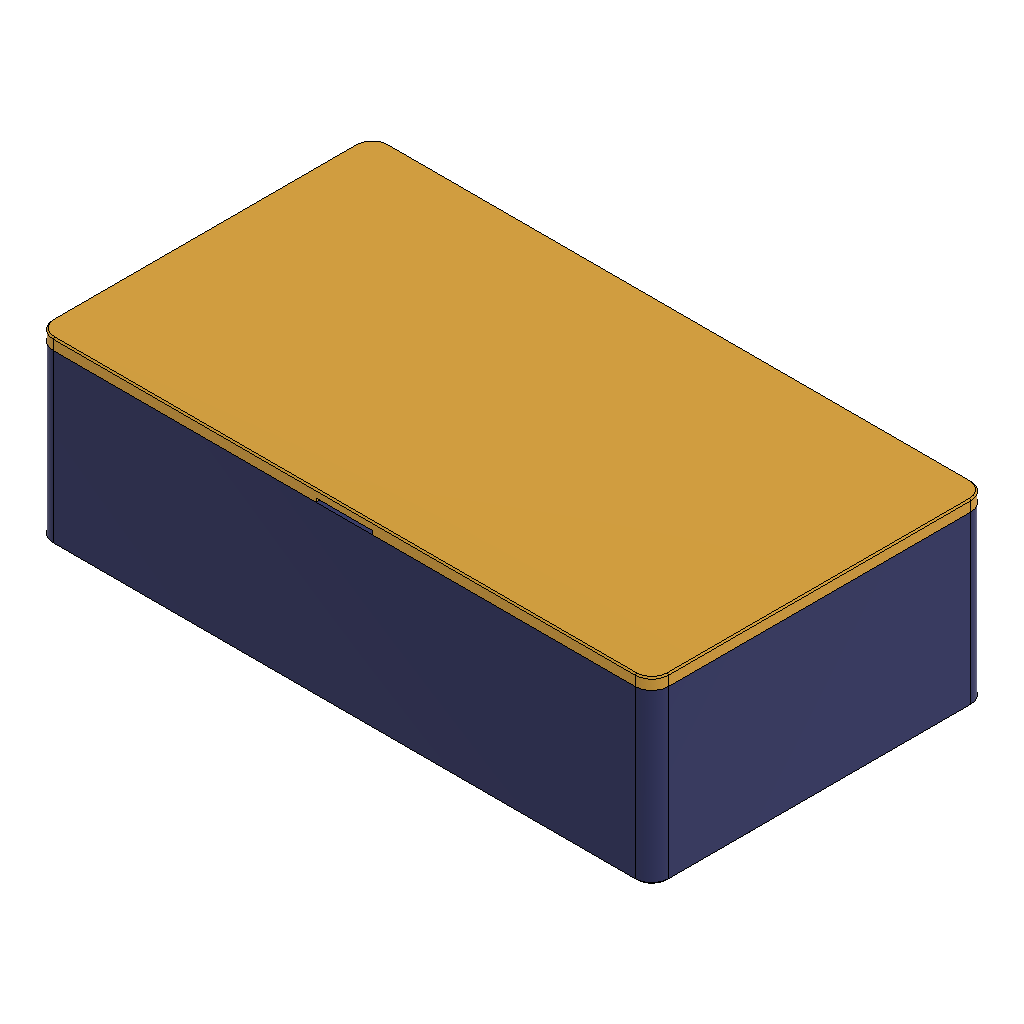
codex snap-fit (Autodesk Fusion 360 design; units mm, degrees)
part number: 2026-10-20-23-35-35-294
Autodesk Fusion 360 part; units mm, degrees
sketch "Box footprint - length x width" plane through (0, 0, 0) normal (0, 0, 1) x (1, 0, 0)
  line L0 (0, 0) -> (110, 0)
  line L1 (110, 0) -> (110, 60)
  line L2 (110, 60) -> (0, 60)
  line L3 (0, 60) -> (0, 0)
  dimension "d5" = 110
  dimension "d6" = 60
  constraint horizontal L0
  constraint horizontal L2
  constraint vertical L1
  constraint vertical L3
  measures "d5" horizontal distance of L0.start L0.end
  measures "d6" vertical distance of L0.end L1.end
extrude "Box outside - height" add sketch "Box footprint - length x width" along normal blind 30 makes body 1
shell "Open top - wall_thickness" thickness 2 removed faces 1 at (36.6667, 40, 30) on bodies 1
fillet "Inside edges - inside_fillet" radius 1 8 edges at (55, 58, 2) (108, 58, 16) (2, 58, 16) (108, 30, 2) (108, 2, 16) (55, 2, 2) (2, 2, 16) (2, 30, 2) on bodies 1
fillet "Outside vertical edges - outside_fillet" radius 3 4 edges at (0, 60, 15) (110, 60, 15) (110, 0, 15) (0, 0, 15) on bodies 1
ref_plane "WorkPlane1" through (0, 0, 30) normal (0, 0, 1) x (1, 0, 0)
sketch "Lid footprint - length x width" plane through (0, 0, 30) normal (0, 0, 1) x (1, 0, 0)
  line L0 (0, 0) -> (110, 0)
  line L1 (110, 0) -> (110, 60)
  line L2 (110, 60) -> (0, 60)
  line L3 (0, 60) -> (0, 0)
  dimension "d25" = 110
  dimension "d26" = 60
  constraint horizontal L0
  constraint horizontal L2
  constraint vertical L1
  constraint vertical L3
  measures "d25" horizontal distance of L0.start L0.end
  measures "d26" vertical distance of L0.end L1.end
extrude "Lid plate - wall_thickness" add sketch "Lid footprint - length x width" along normal blind 2 separate body makes body 2
fillet "Lid corners - outside_fillet" radius 3 4 edges at (0, 60, 31) (110, 60, 31) (110, 0, 31) (0, 0, 31) on bodies 2
ref_plane "WorkPlane61" through (0, 0, 30) normal (0, 0, 1) x (1, 0, 0)
sketch "Continuous shallow locating rim" plane through (0, 0, 30) normal (0, 0, 1) x (1, 0, 0)
  line L0 (2.2, 2.2) -> (107.8, 2.2)
  line L1 (107.8, 2.2) -> (107.8, 57.8)
  line L2 (107.8, 57.8) -> (2.2, 57.8)
  line L3 (2.2, 57.8) -> (2.2, 2.2)
  line L4 (4.2, 4.2) -> (105.8, 4.2)
  line L5 (105.8, 4.2) -> (105.8, 55.8)
  line L6 (105.8, 55.8) -> (4.2, 55.8)
  line L7 (4.2, 55.8) -> (4.2, 4.2)
  dimension "d541" = 2.2
  dimension "d542" = 2.2
  dimension "d543" = 105.6
  dimension "d544" = 55.6
  dimension "d545" = 4.2
  dimension "d546" = 4.2
  dimension "d547" = 101.6
  dimension "d548" = 51.6
  constraint horizontal L0
  constraint horizontal L2
  constraint vertical L1
  constraint vertical L3
  constraint horizontal L4
  constraint horizontal L6
  constraint vertical L5
  constraint vertical L7
  measures "d541" horizontal distance of origin L0.start
  measures "d542" vertical distance of origin L0.start
  measures "d543" horizontal distance of L0.start L0.end
  measures "d544" vertical distance of L0.end L1.end
  measures "d545" horizontal distance of origin L4.start
  measures "d546" vertical distance of origin L4.start
  measures "d547" horizontal distance of L4.start L4.end
  measures "d548" vertical distance of L4.end L5.end
extrude "Continuous locating rim - shallow" add sketch "Continuous shallow locating rim" against normal blind 2 separate body makes body 3
fillet "Locating rim cavity-matching corners" radius 0.8 4 edges at (2.2, 2.2, 29) (107.8, 2.2, 29) (107.8, 57.8, 29) (2.2, 57.8, 29) on bodies 3
combine "Join continuous locating rim to lid" operation add target body 2 tool bodies 3
fillet "Continuous inside rim-to-lid fillet" radius 1 4 edges at (55, 55.8, 30) (105.8, 30, 30) (55, 4.2, 30) (4.2, 30, 30) on bodies 2
ref_plane "WorkPlane62" through (0, 0, 28) normal (0, 0, 1) x (1, 0, 0)
sketch "Front snap 1 tapered root" plane through (0, 0, 28) normal (0, 0, 1) x (1, 0, 0)
  line L0 (20.625, 2.2) -> (34.375, 2.2)
  line L1 (34.375, 2.2) -> (34.375, 4.2)
  line L2 (34.375, 4.2) -> (20.625, 4.2)
  line L3 (20.625, 4.2) -> (20.625, 2.2)
  dimension "d557" = 20.625
  dimension "d558" = 2.2
  dimension "d559" = 13.75
  dimension "d560" = 2
  constraint horizontal L0
  constraint horizontal L2
  constraint vertical L1
  constraint vertical L3
  measures "d557" horizontal distance of origin L0.start
  measures "d558" vertical distance of origin L0.start
  measures "d559" horizontal distance of L0.start L0.end
  measures "d560" vertical distance of L0.end L1.end
ref_plane "WorkPlane63" through (0, 0, 22) normal (0, 0, 1) x (1, 0, 0)
sketch "Front snap 1 tapered tip" plane through (0, 0, 22) normal (0, 0, 1) x (1, 0, 0)
  line L0 (20.625, 2.2) -> (34.375, 2.2)
  line L1 (34.375, 2.2) -> (34.375, 3.45)
  line L2 (34.375, 3.45) -> (20.625, 3.45)
  line L3 (20.625, 3.45) -> (20.625, 2.2)
  dimension "d563" = 20.625
  dimension "d564" = 2.2
  dimension "d565" = 13.75
  dimension "d566" = 1.25
  constraint horizontal L0
  constraint horizontal L2
  constraint vertical L1
  constraint vertical L3
  measures "d563" horizontal distance of origin L0.start
  measures "d564" vertical distance of origin L0.start
  measures "d565" horizontal distance of L0.start L0.end
  measures "d566" vertical distance of L0.end L1.end
loft "Front snap 1 tapered flexible tab" add profiles "Front snap 1 tapered root", "Front snap 1 tapered tip" section 1 section 2 bodies 2
ref_plane "WorkPlane64" through (0, 0, 28) normal (0, 0, 1) x (1, 0, 0)
sketch "Front snap 2 tapered root" plane through (0, 0, 28) normal (0, 0, 1) x (1, 0, 0)
  line L0 (75.625, 2.2) -> (89.375, 2.2)
  line L1 (89.375, 2.2) -> (89.375, 4.2)
  line L2 (89.375, 4.2) -> (75.625, 4.2)
  line L3 (75.625, 4.2) -> (75.625, 2.2)
  dimension "d569" = 75.625
  dimension "d570" = 2.2
  dimension "d571" = 13.75
  dimension "d572" = 2
  constraint horizontal L0
  constraint horizontal L2
  constraint vertical L1
  constraint vertical L3
  measures "d569" horizontal distance of origin L0.start
  measures "d570" vertical distance of origin L0.start
  measures "d571" horizontal distance of L0.start L0.end
  measures "d572" vertical distance of L0.end L1.end
ref_plane "WorkPlane65" through (0, 0, 22) normal (0, 0, 1) x (1, 0, 0)
sketch "Front snap 2 tapered tip" plane through (0, 0, 22) normal (0, 0, 1) x (1, 0, 0)
  line L0 (75.625, 2.2) -> (89.375, 2.2)
  line L1 (89.375, 2.2) -> (89.375, 3.45)
  line L2 (89.375, 3.45) -> (75.625, 3.45)
  line L3 (75.625, 3.45) -> (75.625, 2.2)
  dimension "d575" = 75.625
  dimension "d576" = 2.2
  dimension "d577" = 13.75
  dimension "d578" = 1.25
  constraint horizontal L0
  constraint horizontal L2
  constraint vertical L1
  constraint vertical L3
  measures "d575" horizontal distance of origin L0.start
  measures "d576" vertical distance of origin L0.start
  measures "d577" horizontal distance of L0.start L0.end
  measures "d578" vertical distance of L0.end L1.end
loft "Front snap 2 tapered flexible tab" add profiles "Front snap 2 tapered root", "Front snap 2 tapered tip" section 1 section 2 bodies 2
ref_plane "WorkPlane66" through (0, 0, 28) normal (0, 0, 1) x (1, 0, 0)
sketch "Back snap 1 tapered root" plane through (0, 0, 28) normal (0, 0, 1) x (1, 0, 0)
  line L0 (20.625, 55.8) -> (34.375, 55.8)
  line L1 (34.375, 55.8) -> (34.375, 57.8)
  line L2 (34.375, 57.8) -> (20.625, 57.8)
  line L3 (20.625, 57.8) -> (20.625, 55.8)
  dimension "d581" = 20.625
  dimension "d582" = 55.8
  dimension "d583" = 13.75
  dimension "d584" = 2
  constraint horizontal L0
  constraint horizontal L2
  constraint vertical L1
  constraint vertical L3
  measures "d581" horizontal distance of origin L0.start
  measures "d582" vertical distance of origin L0.start
  measures "d583" horizontal distance of L0.start L0.end
  measures "d584" vertical distance of L0.end L1.end
ref_plane "WorkPlane67" through (0, 0, 22) normal (0, 0, 1) x (1, 0, 0)
sketch "Back snap 1 tapered tip" plane through (0, 0, 22) normal (0, 0, 1) x (1, 0, 0)
  line L0 (20.625, 56.55) -> (34.375, 56.55)
  line L1 (34.375, 56.55) -> (34.375, 57.8)
  line L2 (34.375, 57.8) -> (20.625, 57.8)
  line L3 (20.625, 57.8) -> (20.625, 56.55)
  dimension "d587" = 20.625
  dimension "d588" = 56.55
  dimension "d589" = 13.75
  dimension "d590" = 1.25
  constraint horizontal L0
  constraint horizontal L2
  constraint vertical L1
  constraint vertical L3
  measures "d587" horizontal distance of origin L0.start
  measures "d588" vertical distance of origin L0.start
  measures "d589" horizontal distance of L0.start L0.end
  measures "d590" vertical distance of L0.end L1.end
loft "Back snap 1 tapered flexible tab" add profiles "Back snap 1 tapered root", "Back snap 1 tapered tip" section 1 section 2 bodies 2
ref_plane "WorkPlane68" through (0, 0, 28) normal (0, 0, 1) x (1, 0, 0)
sketch "Back snap 2 tapered root" plane through (0, 0, 28) normal (0, 0, 1) x (1, 0, 0)
  line L0 (75.625, 55.8) -> (89.375, 55.8)
  line L1 (89.375, 55.8) -> (89.375, 57.8)
  line L2 (89.375, 57.8) -> (75.625, 57.8)
  line L3 (75.625, 57.8) -> (75.625, 55.8)
  dimension "d593" = 75.625
  dimension "d594" = 55.8
  dimension "d595" = 13.75
  dimension "d596" = 2
  constraint horizontal L0
  constraint horizontal L2
  constraint vertical L1
  constraint vertical L3
  measures "d593" horizontal distance of origin L0.start
  measures "d594" vertical distance of origin L0.start
  measures "d595" horizontal distance of L0.start L0.end
  measures "d596" vertical distance of L0.end L1.end
ref_plane "WorkPlane69" through (0, 0, 22) normal (0, 0, 1) x (1, 0, 0)
sketch "Back snap 2 tapered tip" plane through (0, 0, 22) normal (0, 0, 1) x (1, 0, 0)
  line L0 (75.625, 56.55) -> (89.375, 56.55)
  line L1 (89.375, 56.55) -> (89.375, 57.8)
  line L2 (89.375, 57.8) -> (75.625, 57.8)
  line L3 (75.625, 57.8) -> (75.625, 56.55)
  dimension "d599" = 75.625
  dimension "d600" = 56.55
  dimension "d601" = 13.75
  dimension "d602" = 1.25
  constraint horizontal L0
  constraint horizontal L2
  constraint vertical L1
  constraint vertical L3
  measures "d599" horizontal distance of origin L0.start
  measures "d600" vertical distance of origin L0.start
  measures "d601" horizontal distance of L0.start L0.end
  measures "d602" vertical distance of L0.end L1.end
loft "Back snap 2 tapered flexible tab" add profiles "Back snap 2 tapered root", "Back snap 2 tapered tip" section 1 section 2 bodies 2
fillet "Eight strengthened rim-to-tab end transitions" radius 1 8 edges at (75.625, 56.8, 28) (89.375, 56.8, 28) (89.375, 3.2, 28) (20.625, 56.8, 28) (34.375, 56.8, 28) (75.625, 3.2, 28) (34.375, 3.2, 28) (20.625, 3.2, 28) on bodies 2
ref_plane "WorkPlane70" through (20.425, 0, 0) normal (1, 0, 0) x (0, 1, 0)
sketch "Front snap 1 mating groove" plane through (20.425, 0, 0) normal (1, 0, 0) x (0, 0, -1)
  circle A0 centre (-23.5, 2.2) radius 0.8
  dimension "d607" = 23.5
  dimension "d608" = 2.2
  dimension "d609" = 0.8
  measures "d607" horizontal distance of origin A0.centre
  measures "d608" vertical distance of origin A0.centre
  measures "d609" radius of A0
extrude "Front snap 1 groove" cut sketch "Front snap 1 mating groove" along normal blind 14.15 bodies 1
ref_plane "WorkPlane71" through (75.425, 0, 0) normal (1, 0, 0) x (0, 1, 0)
sketch "Front snap 2 mating groove" plane through (75.425, 0, 0) normal (1, 0, 0) x (0, 0, -1)
  circle A0 centre (-23.5, 2.2) radius 0.8
  dimension "d614" = 23.5
  dimension "d615" = 2.2
  dimension "d616" = 0.8
  measures "d614" horizontal distance of origin A0.centre
  measures "d615" vertical distance of origin A0.centre
  measures "d616" radius of A0
extrude "Front snap 2 groove" cut sketch "Front snap 2 mating groove" along normal blind 14.15 bodies 1
ref_plane "WorkPlane72" through (20.425, 0, 0) normal (1, 0, 0) x (0, 1, 0)
sketch "Back snap 1 mating groove" plane through (20.425, 0, 0) normal (1, 0, 0) x (0, 0, -1)
  circle A0 centre (-23.5, 57.8) radius 0.8
  dimension "d621" = 23.5
  dimension "d622" = 57.8
  dimension "d623" = 0.8
  measures "d621" horizontal distance of origin A0.centre
  measures "d622" vertical distance of origin A0.centre
  measures "d623" radius of A0
extrude "Back snap 1 groove" cut sketch "Back snap 1 mating groove" along normal blind 14.15 bodies 1
ref_plane "WorkPlane73" through (75.425, 0, 0) normal (1, 0, 0) x (0, 1, 0)
sketch "Back snap 2 mating groove" plane through (75.425, 0, 0) normal (1, 0, 0) x (0, 0, -1)
  circle A0 centre (-23.5, 57.8) radius 0.8
  dimension "d628" = 23.5
  dimension "d629" = 57.8
  dimension "d630" = 0.8
  measures "d628" horizontal distance of origin A0.centre
  measures "d629" vertical distance of origin A0.centre
  measures "d630" radius of A0
extrude "Back snap 2 groove" cut sketch "Back snap 2 mating groove" along normal blind 14.15 bodies 1
ref_plane "WorkPlane74" through (20.625, 0, 0) normal (1, 0, 0) x (0, 1, 0)
sketch "Front snap 1 semicircular bead" plane through (20.625, 0, 0) normal (1, 0, 0) x (0, 0, -1)
  circle A0 centre (-23.5, 2.2) radius 0.75
  dimension "d635" = 23.5
  dimension "d636" = 2.2
  dimension "d637" = 0.75
  measures "d635" horizontal distance of origin A0.centre
  measures "d636" vertical distance of origin A0.centre
  measures "d637" radius of A0
extrude "Front snap 1 retaining bead" add sketch "Front snap 1 semicircular bead" along normal blind 13.75 bodies 2
ref_plane "WorkPlane75" through (75.625, 0, 0) normal (1, 0, 0) x (0, 1, 0)
sketch "Front snap 2 semicircular bead" plane through (75.625, 0, 0) normal (1, 0, 0) x (0, 0, -1)
  circle A0 centre (-23.5, 2.2) radius 0.75
  dimension "d642" = 23.5
  dimension "d643" = 2.2
  dimension "d644" = 0.75
  measures "d642" horizontal distance of origin A0.centre
  measures "d643" vertical distance of origin A0.centre
  measures "d644" radius of A0
extrude "Front snap 2 retaining bead" add sketch "Front snap 2 semicircular bead" along normal blind 13.75 bodies 2
ref_plane "WorkPlane76" through (20.625, 0, 0) normal (1, 0, 0) x (0, 1, 0)
sketch "Back snap 1 semicircular bead" plane through (20.625, 0, 0) normal (1, 0, 0) x (0, 0, -1)
  circle A0 centre (-23.5, 57.8) radius 0.75
  dimension "d649" = 23.5
  dimension "d650" = 57.8
  dimension "d651" = 0.75
  measures "d649" horizontal distance of origin A0.centre
  measures "d650" vertical distance of origin A0.centre
  measures "d651" radius of A0
extrude "Back snap 1 retaining bead" add sketch "Back snap 1 semicircular bead" along normal blind 13.75 bodies 2
ref_plane "WorkPlane77" through (75.625, 0, 0) normal (1, 0, 0) x (0, 1, 0)
sketch "Back snap 2 semicircular bead" plane through (75.625, 0, 0) normal (1, 0, 0) x (0, 0, -1)
  circle A0 centre (-23.5, 57.8) radius 0.75
  dimension "d656" = 23.5
  dimension "d657" = 57.8
  dimension "d658" = 0.75
  measures "d656" horizontal distance of origin A0.centre
  measures "d657" vertical distance of origin A0.centre
  measures "d658" radius of A0
extrude "Back snap 2 retaining bead" add sketch "Back snap 2 semicircular bead" along normal blind 13.75 bodies 2
ref_plane "WorkPlane96" through (50, 0, 0) normal (1, 0, 0) x (0, 1, 0)
sketch "Front beveled pick-entry profile" plane through (50, 0, 0) normal (1, 0, 0) x (0, 0, -1)
  line L0 (-30, 0) -> (-30.6667, 0)
  line L1 (-30.6667, 0) -> (-30, 2)
  line L2 (-30, 2) -> (-30, 0)
  dimension "d810" = 30
  dimension "d811" = 0.6667
  dimension "d812" = 2
  constraint horizontal L0
  constraint vertical L2
  constraint horizontal origin L0.start
  measures "d810" horizontal distance of origin L0.start
  measures "d811" horizontal distance of L0.start L0.end
  measures "d812" vertical distance of L0.start L1.end
extrude "Front beveled pick-entry notch between snaps" cut sketch "Front beveled pick-entry profile" along normal blind 10 bodies 2
ref_plane "WorkPlane97" through (50, 0, 0) normal (1, 0, 0) x (0, 1, 0)
sketch "Back beveled pick-entry profile" plane through (50, 0, 0) normal (1, 0, 0) x (0, 0, -1)
  line L0 (-30, 60) -> (-30.6667, 60)
  line L1 (-30.6667, 60) -> (-30, 58)
  line L2 (-30, 58) -> (-30, 60)
  dimension "d817" = 30
  dimension "d818" = 60
  dimension "d819" = 0.6667
  dimension "d820" = 2
  constraint horizontal L0
  constraint vertical L2
  measures "d817" horizontal distance of origin L0.start
  measures "d818" vertical distance of origin L0.start
  measures "d819" horizontal distance of L0.start L0.end
  measures "d820" vertical distance of L0.start L1.end
extrude "Back beveled pick-entry notch between snaps" cut sketch "Back beveled pick-entry profile" along normal blind 10 bodies 2
chamfer "Chamfer1" distance 0.25 angle 45 8 edges at (55, 0, 32) (109.1213, 0.8787, 32) (110, 30, 32) (109.1213, 59.1213, 32) (55, 60, 32) (0.8787, 59.1213, 32) (0, 30, 32) (0.8787, 0.8787, 32) tangent chain off on bodies 1 2
chamfer "Chamfer1" distance 0.25 angle 45 8 edges at (55, 0, 0) (109.1213, 0.8787, 0) (110, 30, 0) (109.1213, 59.1213, 0) (55, 60, 0) (0.8787, 59.1213, 0) (0, 30, 0) (0.8787, 0.8787, 0) tangent chain off on bodies 1 2
equation "length = 110 mm" comment "Outside length"
equation "width = 60 mm" comment "Outside width"
equation "height = 30 mm" comment "Outside height"
equation "wall_thickness = 2 mm" comment "Side walls and bottom thickness"
equation "d5 = length"
equation "d6 = width"
equation "d7 = height"
equation "d9 = wall_thickness"
equation "inside_fillet = wall_thickness / 2" comment "Radius for four inside vertical and four inside bottom edges"
equation "d12 = inside_fillet"
equation "outside_fillet = 3 mm" comment "Radius for the four vertical outside edges"
equation "d15 = outside_fillet"
equation "lid_gap = 0.2 mm" comment "Lateral locating-rim/tab-to-wall clearance per side; seam and groove clearances now separate"
equation "lid_thickness = wall_thickness" comment "Lid plate thickness follows box wall"
equation "lip_depth = 4 * wall_thickness" comment "Length of the four flexible insertion tabs"
equation "lip_radius = 3 * wall_thickness / 8" comment "Retaining bead radius; increased for stronger engagement; groove uses snap_clearance"
equation "snap_thickness = 5 * wall_thickness / 8" comment "Tapered tab thickness at free tip; root uses snap_root_thickness"
equation "snap_length = length / 8" comment "Width of each of the four tabs; two per long side"
equation "d23 = height + lid_seam_gap"
equation "d25 = abs(( length ) - ( 0 mm ))"
equation "d26 = abs(( width ) - ( 0 mm ))"
equation "d27 = lid_thickness"
equation "d30 = outside_fillet"
equation "snap_root_fillet = wall_thickness / 2" comment "Rounded end transitions where each tab emerges from the locating rim"
equation "snap_offset = length / 4" comment "Tab center distance from each short end"
equation "rim_depth = wall_thickness" comment "Shallow continuous locating-rim insertion depth"
equation "rim_thickness = wall_thickness" comment "Continuous locating-rim width and nominal tab-root thickness"
equation "rim_corner_radius = inside_fillet - lid_gap" comment "Outer locating-rim corner radius matching the offset box cavity"
equation "snap_root_thickness = rim_thickness" comment "Tab thickness at rim attachment"
equation "rim_inside_fillet = wall_thickness / 2" comment "Continuous inside rim-to-lid-plate fillet"
equation "d539 = height + lid_seam_gap"
equation "d541 = abs(wall_thickness + lid_gap)"
equation "d542 = abs(wall_thickness + lid_gap)"
equation "d543 = abs(( length - wall_thickness - lid_gap ) - ( wall_thickness + lid_gap ))"
equation "d544 = abs(( width - wall_thickness - lid_gap ) - ( wall_thickness + lid_gap ))"
equation "d545 = abs(wall_thickness + lid_gap + rim_thickness)"
equation "d546 = abs(wall_thickness + lid_gap + rim_thickness)"
equation "d547 = abs(( length - wall_thickness - lid_gap - rim_thickness ) - ( wall_thickness + lid_gap + rim_thickness ))"
equation "d548 = abs(( width - wall_thickness - lid_gap - rim_thickness ) - ( wall_thickness + lid_gap + rim_thickness ))"
equation "d549 = -rim_depth"
equation "d552 = rim_corner_radius"
equation "d554 = rim_inside_fillet"
equation "d555 = height + lid_seam_gap - rim_depth"
equation "d557 = abs(( snap_offset ) - snap_length / 2)"
equation "d558 = abs(wall_thickness + lid_gap)"
equation "d559 = abs(( ( snap_offset ) + snap_length / 2 ) - ( ( snap_offset ) - snap_length / 2 ))"
equation "d560 = abs(( wall_thickness + lid_gap + snap_root_thickness ) - ( wall_thickness + lid_gap ))"
equation "d561 = height + lid_seam_gap - lip_depth"
equation "d563 = abs(( snap_offset ) - snap_length / 2)"
equation "d564 = abs(wall_thickness + lid_gap)"
equation "d565 = abs(( ( snap_offset ) + snap_length / 2 ) - ( ( snap_offset ) - snap_length / 2 ))"
equation "d566 = abs(( wall_thickness + lid_gap + snap_thickness ) - ( wall_thickness + lid_gap ))"
equation "d567 = height + lid_seam_gap - rim_depth"
equation "d569 = abs(( length - snap_offset ) - snap_length / 2)"
equation "d570 = abs(wall_thickness + lid_gap)"
equation "d571 = abs(( ( length - snap_offset ) + snap_length / 2 ) - ( ( length - snap_offset ) - snap_length / 2 ))"
equation "d572 = abs(( wall_thickness + lid_gap + snap_root_thickness ) - ( wall_thickness + lid_gap ))"
equation "d573 = height + lid_seam_gap - lip_depth"
equation "d575 = abs(( length - snap_offset ) - snap_length / 2)"
equation "d576 = abs(wall_thickness + lid_gap)"
equation "d577 = abs(( ( length - snap_offset ) + snap_length / 2 ) - ( ( length - snap_offset ) - snap_length / 2 ))"
equation "d578 = abs(( wall_thickness + lid_gap + snap_thickness ) - ( wall_thickness + lid_gap ))"
equation "d579 = height + lid_seam_gap - rim_depth"
equation "d581 = abs(( snap_offset ) - snap_length / 2)"
equation "d582 = abs(width - wall_thickness - lid_gap - snap_root_thickness)"
equation "d583 = abs(( ( snap_offset ) + snap_length / 2 ) - ( ( snap_offset ) - snap_length / 2 ))"
equation "d584 = abs(( width - wall_thickness - lid_gap ) - ( width - wall_thickness - lid_gap - snap_root_thickness ))"
equation "d585 = height + lid_seam_gap - lip_depth"
equation "d587 = abs(( snap_offset ) - snap_length / 2)"
equation "d588 = abs(width - wall_thickness - lid_gap - snap_thickness)"
equation "d589 = abs(( ( snap_offset ) + snap_length / 2 ) - ( ( snap_offset ) - snap_length / 2 ))"
equation "d590 = abs(( width - wall_thickness - lid_gap ) - ( width - wall_thickness - lid_gap - snap_thickness ))"
equation "d591 = height + lid_seam_gap - rim_depth"
equation "d593 = abs(( length - snap_offset ) - snap_length / 2)"
equation "d594 = abs(width - wall_thickness - lid_gap - snap_root_thickness)"
equation "d595 = abs(( ( length - snap_offset ) + snap_length / 2 ) - ( ( length - snap_offset ) - snap_length / 2 ))"
equation "d596 = abs(( width - wall_thickness - lid_gap ) - ( width - wall_thickness - lid_gap - snap_root_thickness ))"
equation "d597 = height + lid_seam_gap - lip_depth"
equation "d599 = abs(( length - snap_offset ) - snap_length / 2)"
equation "d600 = abs(width - wall_thickness - lid_gap - snap_thickness)"
equation "d601 = abs(( ( length - snap_offset ) + snap_length / 2 ) - ( ( length - snap_offset ) - snap_length / 2 ))"
equation "d602 = abs(( width - wall_thickness - lid_gap ) - ( width - wall_thickness - lid_gap - snap_thickness ))"
equation "d604 = snap_root_fillet"
equation "d605 = ( snap_offset ) - snap_length / 2 - lid_gap"
equation "d607 = abs(-( height + lid_seam_gap - lip_depth + 2 * lip_radius ))"
equation "d608 = abs(( wall_thickness + lid_gap ))"
equation "d609 = lip_radius + snap_clearance"
equation "d610 = snap_length + 2 * lid_gap"
equation "d612 = ( length - snap_offset ) - snap_length / 2 - lid_gap"
equation "d614 = abs(-( height + lid_seam_gap - lip_depth + 2 * lip_radius ))"
equation "d615 = abs(( wall_thickness + lid_gap ))"
equation "d616 = lip_radius + snap_clearance"
equation "d617 = snap_length + 2 * lid_gap"
equation "d619 = ( snap_offset ) - snap_length / 2 - lid_gap"
equation "d621 = abs(-( height + lid_seam_gap - lip_depth + 2 * lip_radius ))"
equation "d622 = abs(( width - wall_thickness - lid_gap ))"
equation "d623 = lip_radius + snap_clearance"
equation "d624 = snap_length + 2 * lid_gap"
equation "d626 = ( length - snap_offset ) - snap_length / 2 - lid_gap"
equation "d628 = abs(-( height + lid_seam_gap - lip_depth + 2 * lip_radius ))"
equation "d629 = abs(( width - wall_thickness - lid_gap ))"
equation "d630 = lip_radius + snap_clearance"
equation "d631 = snap_length + 2 * lid_gap"
equation "d633 = ( snap_offset ) - snap_length / 2"
equation "d635 = abs(-( height + lid_seam_gap - lip_depth + 2 * lip_radius ))"
equation "d636 = abs(( wall_thickness + lid_gap ))"
equation "d637 = lip_radius"
equation "d638 = snap_length"
equation "d640 = ( length - snap_offset ) - snap_length / 2"
equation "d642 = abs(-( height + lid_seam_gap - lip_depth + 2 * lip_radius ))"
equation "d643 = abs(( wall_thickness + lid_gap ))"
equation "d644 = lip_radius"
equation "d645 = snap_length"
equation "d647 = ( snap_offset ) - snap_length / 2"
equation "d649 = abs(-( height + lid_seam_gap - lip_depth + 2 * lip_radius ))"
equation "d650 = abs(( width - wall_thickness - lid_gap ))"
equation "d651 = lip_radius"
equation "d652 = snap_length"
equation "d654 = ( length - snap_offset ) - snap_length / 2"
equation "d656 = abs(-( height + lid_seam_gap - lip_depth + 2 * lip_radius ))"
equation "d657 = abs(( width - wall_thickness - lid_gap ))"
equation "d658 = lip_radius"
equation "d659 = snap_length"
equation "lid_seam_gap = 0 mm" comment "Vertical gap under lid plate; zero seats the lid on the box rim"
equation "snap_clearance = 0.05 mm" comment "Radial bead-to-groove clearance, independent of locating clearance; controls vertical play"
equation "pry_width = 5 * wall_thickness" comment "Pick-entry notch width centered between the two long-side tabs"
equation "pry_depth = lid_thickness / 3" comment "Beveled recess height at lid outer edge"
equation "pry_reach = wall_thickness" comment "Bevel reach inward from lid edge; should stop before locating rim"
equation "d808 = length / 2 - pry_width / 2"
equation "d810 = height + lid_seam_gap"
equation "d811 = pry_depth"
equation "d812 = pry_reach"
equation "d813 = pry_width"
equation "d815 = length / 2 - pry_width / 2"
equation "d817 = height + lid_seam_gap"
equation "d818 = width"
equation "d819 = pry_depth"
equation "d820 = pry_reach"
equation "d821 = pry_width"
equation "bed_chamfer = 0.25 mm" comment "anti-elephant foot chamfer"
equation "d824 = bed_chamfer"
equation "d825 = bed_chamfer"
equation "d685 = abs(( ( length - snap_offset ) - ( release_width - release_height ) / 2 ))"
equation "d686 = abs(-( height + lid_gap - lip_depth + 2 * lip_radius ))"
equation "d687 = release_radius"
equation "d688 = wall_thickness + 2 * lid_gap"
equation "d692 = abs(( ( length - snap_offset ) + ( release_width - release_height ) / 2 ))"
equation "d693 = abs(-( height + lid_gap - lip_depth + 2 * lip_radius ))"
equation "d694 = release_radius"
equation "d695 = wall_thickness + 2 * lid_gap"
equation "d699 = abs(( ( length - snap_offset ) - ( release_width - release_height ) / 2 ))"
equation "d700 = abs(-( ( height + lid_gap - lip_depth + 2 * lip_radius ) - release_radius ))"
equation "d701 = abs(( ( ( length - snap_offset ) + ( release_width - release_height ) / 2 ) ) - ( ( ( length - snap_offset ) - ( release_width - release_height ) / 2 ) ))"
equation "d702 = abs(( -( ( height + lid_gap - lip_depth + 2 * lip_radius ) + release_radius ) ) - ( -( ( height + lid_gap - lip_depth + 2 * lip_radius ) - release_radius ) ))"
equation "d703 = wall_thickness + 2 * lid_gap"
equation "d705 = width - wall_thickness - lid_gap"
equation "d707 = abs(( ( snap_offset ) - ( release_width - release_height ) / 2 ))"
equation "d708 = abs(-( height + lid_gap - lip_depth + 2 * lip_radius ))"
equation "d709 = release_radius"
equation "d710 = wall_thickness + 2 * lid_gap"
equation "d712 = width - wall_thickness - lid_gap"
equation "d714 = abs(( ( snap_offset ) + ( release_width - release_height ) / 2 ))"
equation "d715 = abs(-( height + lid_gap - lip_depth + 2 * lip_radius ))"
equation "d716 = release_radius"
equation "d717 = wall_thickness + 2 * lid_gap"
equation "d719 = width - wall_thickness - lid_gap"
equation "d721 = abs(( ( snap_offset ) - ( release_width - release_height ) / 2 ))"
equation "d722 = abs(-( ( height + lid_gap - lip_depth + 2 * lip_radius ) - release_radius ))"
equation "d723 = abs(( ( ( snap_offset ) + ( release_width - release_height ) / 2 ) ) - ( ( ( snap_offset ) - ( release_width - release_height ) / 2 ) ))"
equation "d724 = abs(( -( ( height + lid_gap - lip_depth + 2 * lip_radius ) + release_radius ) ) - ( -( ( height + lid_gap - lip_depth + 2 * lip_radius ) - release_radius ) ))"
equation "d725 = wall_thickness + 2 * lid_gap"
equation "d727 = width - wall_thickness - lid_gap"
equation "d729 = abs(( ( length - snap_offset ) - ( release_width - release_height ) / 2 ))"
equation "d730 = abs(-( height + lid_gap - lip_depth + 2 * lip_radius ))"
equation "d731 = release_radius"
equation "d732 = wall_thickness + 2 * lid_gap"
equation "d734 = width - wall_thickness - lid_gap"
equation "d736 = abs(( ( length - snap_offset ) + ( release_width - release_height ) / 2 ))"
equation "d737 = abs(-( height + lid_gap - lip_depth + 2 * lip_radius ))"
equation "d738 = release_radius"
equation "d739 = wall_thickness + 2 * lid_gap"
equation "d741 = width - wall_thickness - lid_gap"
equation "d743 = abs(( ( length - snap_offset ) - ( release_width - release_height ) / 2 ))"
equation "d744 = abs(-( ( height + lid_gap - lip_depth + 2 * lip_radius ) - release_radius ))"
equation "d745 = abs(( ( ( length - snap_offset ) + ( release_width - release_height ) / 2 ) ) - ( ( ( length - snap_offset ) - ( release_width - release_height ) / 2 ) ))"
equation "d746 = abs(( -( ( height + lid_gap - lip_depth + 2 * lip_radius ) + release_radius ) ) - ( -( ( height + lid_gap - lip_depth + 2 * lip_radius ) - release_radius ) ))"
equation "d747 = wall_thickness + 2 * lid_gap"
equation "d749 = height - coupon_height"
equation "d751 = abs(snap_offset - snap_length / 2 - ( coupon_margin + coupon_end_clearance ))"
equation "d752 = abs(( snap_offset + snap_length / 2 + ( coupon_margin + coupon_end_clearance ) ) - ( snap_offset - snap_length / 2 - ( coupon_margin + coupon_end_clearance ) ))"
equation "d753 = abs(( wall_thickness ) - ( 0 mm ))"
equation "d754 = coupon_height"
equation "d761 = abs(length + coupon_spacing)"
equation "d762 = abs(( length + coupon_spacing + snap_length + 2 * ( coupon_margin + coupon_end_clearance ) ) - ( length + coupon_spacing ))"
equation "d763 = abs(( coupon_foot_depth ) - ( 0 mm ))"
equation "d764 = wall_thickness"
equation "d768 = abs(length + coupon_spacing)"
equation "d769 = abs(( length + coupon_spacing + wall_thickness ) - ( length + coupon_spacing ))"
equation "d770 = abs(( coupon_foot_depth ) - ( 0 mm ))"
equation "d771 = abs(length + coupon_spacing + snap_length + 2 * ( coupon_margin + coupon_end_clearance ) - wall_thickness)"
equation "d772 = abs(( length + coupon_spacing + snap_length + 2 * ( coupon_margin + coupon_end_clearance ) ) - ( length + coupon_spacing + snap_length + 2 * ( coupon_margin + coupon_end_clearance ) - wall_thickness ))"
equation "d773 = abs(( coupon_foot_depth ) - ( 0 mm ))"
equation "d774 = coupon_height"
equation "d776 = height + lid_gap - lip_depth"
equation "d778 = abs(snap_offset - snap_length / 2 - coupon_margin)"
equation "d779 = abs(( snap_offset + snap_length / 2 + coupon_margin ) - ( snap_offset - snap_length / 2 - coupon_margin ))"
equation "d780 = abs(( coupon_foot_depth ) - ( 0 mm ))"
equation "d781 = lip_depth + lid_thickness"
equation "d784 = length + coupon_spacing - ( snap_offset - snap_length / 2 - coupon_margin )"
equation "d785 = 2 * coupon_foot_depth + coupon_spacing"
equation "d786 = height + lid_gap + lid_thickness"
equation "coupon_end_clearance = wall_thickness + lid_gap" comment "Extra length at each wall-coupon end: accommodates end-return thickness plus fit clearance; does not alter lid coupon"
named bodies: "Parametric open-top box", "Snap-fit lid"
